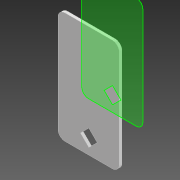
# Autodesk Inventor part: clear_front
Saved by Autodesk Inventor 2020.1 (Build 241239000, 239)
## iProperties
Created: 2026-10-16
Part Number: clear_front
Material: Polycarbonate, Clear
Document SubType Name: Modeling
Designer: willn
Density: 1.2 g/cm^3
Appearance: Polycarbonate - Clear
Author: willn
Autodesk Inventor part; units mm, degrees
ref_plane "YZ Plane" through (0, 0, 0) normal (1, 0, 0) x (0, 1, 0)
ref_plane "XZ Plane" through (0, 0, 0) normal (0, 1, 0) x (-1, 0, 0)
ref_plane "XY Plane" through (0, 0, 0) normal (0, 0, 1) x (1, 0, 0)
sketch "Sketch1" plane through (0, 0, 0) normal (0, 0, 1) x (1, 0, 0)
  line L0 (-33.5, 53.4) -> (-33.5, -53.4)
  arc A0 (-26, 60.9) -> (-33.5, 53.4) centre (-26, 53.4) ccw
  line L1 (26, 60.9) -> (-26, 60.9)
  arc A1 (33.5, 53.4) -> (26, 60.9) centre (26, 53.4) ccw
  line L2 (33.5, -53.4) -> (33.5, 53.4)
  arc A2 (26, -60.9) -> (33.5, -53.4) centre (26, -53.4) ccw
  line L3 (-26, -60.9) -> (26, -60.9)
  arc A3 (-33.5, -53.4) -> (-26, -60.9) centre (-26, -53.4) ccw
  point P0 (0, 0)
  constraints: 8 end point, 8 point on circle, 4 centre point, 2 horizontal, 2 vertical, 16 other
extrude "Extrusion1" add sketch "Sketch1" along normal blind 3
sketch "Sketch2" plane through (0, 0, 3) normal (0, 0, 1) x (1, 0, 0)
  arc A0 (-8.1196, -44.3325) -> (-8.1777, -44.4882) centre (-7.9782, -44.4739) ccw construction
  arc A1 (-8.1777, -44.4882) -> (-8.1196, -44.6154) centre (-7.9782, -44.4739) ccw construction
  arc A2 (0.2384, -36.072) -> (0.0828, -36.1301) centre (0.2242, -36.2715) ccw construction
  arc A3 (0.3656, -36.1301) -> (0.2384, -36.072) centre (0.2242, -36.2715) ccw construction
  arc A4 (0.21, -52.8759) -> (0.3656, -52.8178) centre (0.2242, -52.6764) ccw construction
  arc A5 (0.0828, -52.8178) -> (0.21, -52.8759) centre (0.2242, -52.6764) ccw construction
  arc A6 (8.5681, -44.6154) -> (8.6261, -44.4597) centre (8.4266, -44.4739) ccw construction
  arc A7 (8.6261, -44.4597) -> (8.5681, -44.3325) centre (8.4266, -44.4739) ccw construction
  line L0 (8.4266, -44.4739) -> (0.2242, -52.6764) construction
  line L1 (0.2242, -52.6764) -> (-7.9782, -44.4739) construction
  line L2 (0.2242, -36.2715) -> (-7.9782, -44.4739) construction
  line L3 (0.2242, -36.2715) -> (8.4266, -44.4739) construction
  line L4 (-8.2611, -44.4739) -> (0.2242, -52.9592) construction
  line L5 (0.2242, -52.9592) -> (8.7095, -44.4739) construction
  line L6 (8.7095, -44.4739) -> (0.2242, -35.9886) construction
  line L7 (0.2242, -35.9886) -> (-8.2611, -44.4739) construction
  line L8 (-8.9682, -44.4739) -> (0.2242, -53.6663)
  line L9 (0.2242, -53.6663) -> (9.4166, -44.4739)
  line L10 (9.4166, -44.4739) -> (0.2242, -35.2815)
  line L11 (0.2242, -35.2815) -> (-8.9682, -44.4739)
  point P0 (0, 0)
  point P1 (-0.5536, -36.7665)
  dimension "d2" = 0.5
  constraints: 24 end point, 16 point on circle, 8 centre point, 6 perpendicular, 1 point on line, 35 other
  measures "d2" distance between parallel lines of L7 L11
extrude "Extrusion2" cut sketch "Sketch2" against normal blind 10
body "Solid1"
